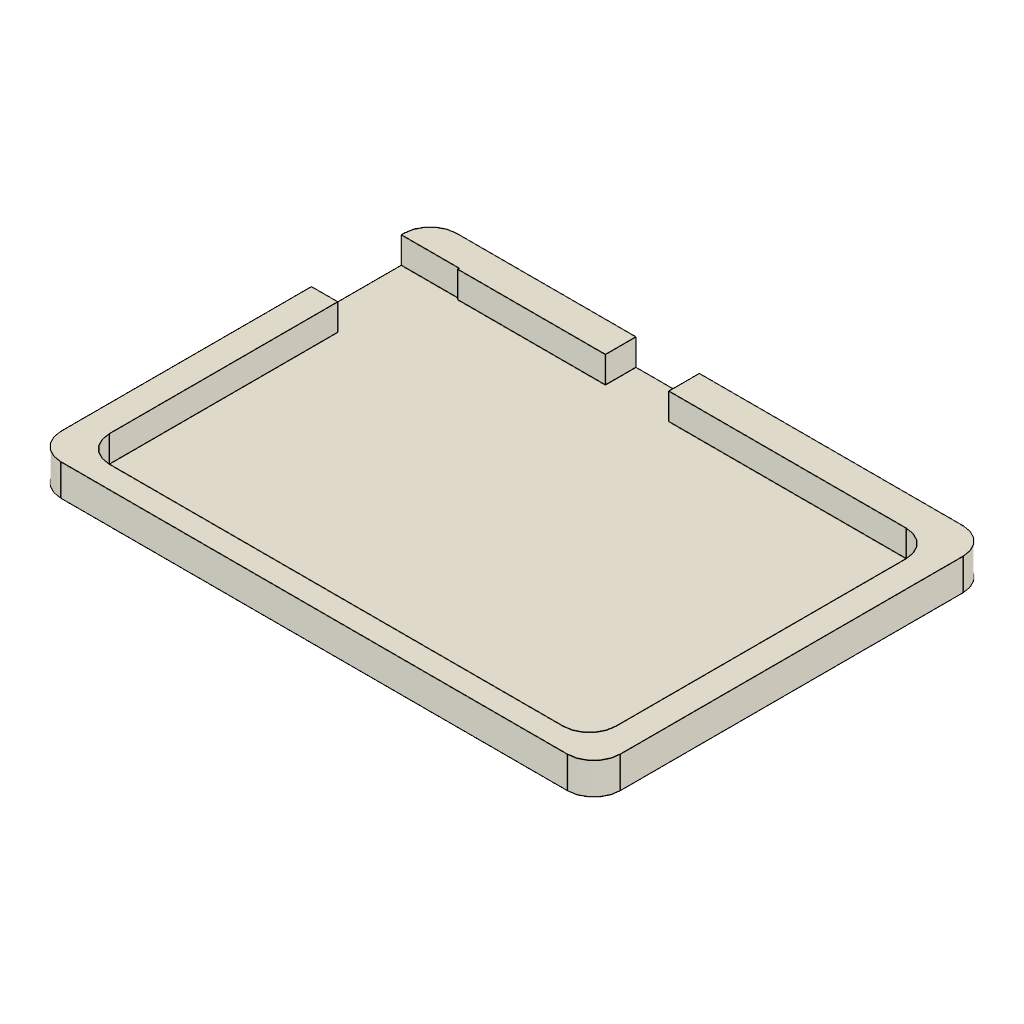
air monitor assesmbly model (Autodesk Fusion 360 archive; units mm, degrees)
design "air monitor"
part number: 2026-10-24-11-17-40-774
Autodesk Fusion 360 part; units mm, degrees
sketch "Sketch1" plane through (0, 0, 0) normal (0, 1, 0) x (1, 0, 0)
  line L0 (-50, 30) -> (46, 30)
  line L1 (46, 30) -> (46, -35)
  line L2 (46, -35) -> (-50, -35)
  line L3 (-50, -35) -> (-50, 30)
  line L4 (-55, 35.8003) -> (51, 35.8003)
  line L5 (51, 35.8003) -> (51, -39.1997)
  line L6 (51, -39.1997) -> (-55, -39.1997)
  line L7 (-55, -39.1997) -> (-55, 35.8003)
  dimension "d1" = 96
  dimension "d2" = 65
  dimension "d3" = 106
  dimension "d4" = 75
  dimension "d5" = 5
  constraint horizontal L0
  constraint vertical L1
  constraint horizontal L2
  constraint vertical L3
  constraint horizontal L4
  constraint vertical L5
  constraint horizontal L6
  constraint vertical L7
  measures "d1" distance of L0.start L0.end
  measures "d2" distance of L0.start L2.end
  measures "d3" distance of L4.start L4.end
  measures "d4" distance of L4.start L6.end
  measures "d5" distance of L3 L7
extrude "Extrude1" add sketch "Sketch1" along normal blind 6
extrude "Extrude2" add sketch "Sketch1" along normal blind 1 contours L0 L1 L2 L3
fillet "Fillet1" radius 5 1 edges at (-55, 3, 39.1997)
fillet "Fillet2" radius 5 7 edges at (51, 3, 39.1997) (51, 3, -35.8003) (-55, 3, -35.8003) (46, 3.5, 35) (-50, 3.5, -30) (46, 3.5, -30) (-50, 3.5, 35)
sketch "Sketch3" plane through (0, 0, 0) normal (0, 0, 1) x (1, 0, 0)
  line L0 (-4, 6) -> (-16, 6)
  line L1 (-16, 6) -> (-16, 1)
  line L2 (-16, 1) -> (-4, 1)
  line L3 (-4, 1) -> (-4, 6)
  line L4 (-50, 6) -> (-50, 0)
  dimension "d14" = 12
  dimension "d15" = 5
  dimension "d16" = 34
  constraint horizontal L0
  constraint vertical L1
  constraint horizontal L2
  constraint vertical L3
  measures "d14" distance of L0.start L0.end
  measures "d15" distance of L0.start L2.end
  measures "d16" distance of L1 L4
extrude "Extrude3" cut sketch "Sketch3" against normal blind 36
sketch "Sketch5" plane through (-55, 0, 0) normal (-1, 0, 0) x (0, 0, 1)
  line L0 (-30.8003, 6) -> (-30.8003, 0)
  line L1 (-30.8003, 0) -> (34.1997, 0)
  line L2 (34.1997, 0) -> (34.1997, 6)
  line L3 (34.1997, 6) -> (-30.8003, 6)
  line L4 (-30.3003, 6) -> (-13.3003, 6)
  line L5 (-13.3003, 6) -> (-13.3003, 1)
  line L6 (-13.3003, 1) -> (-30.3003, 1)
  line L7 (-30.3003, 1) -> (-30.3003, 6)
  dimension "d21" = 17
  dimension "d22" = 5
  dimension "d23" = 0.5
  constraint horizontal L4
  constraint vertical L5
  constraint horizontal L6
  constraint vertical L7
  constraint coincident L3 L4.start
  measures "d21" distance of L4.start L4.end
  measures "d22" distance of L4.start L6.end
  measures "d23" distance of L0 L7
extrude "Extrude4" cut sketch "Sketch5" against normal blind 11 contours L3 L4 L5 L6 L7
